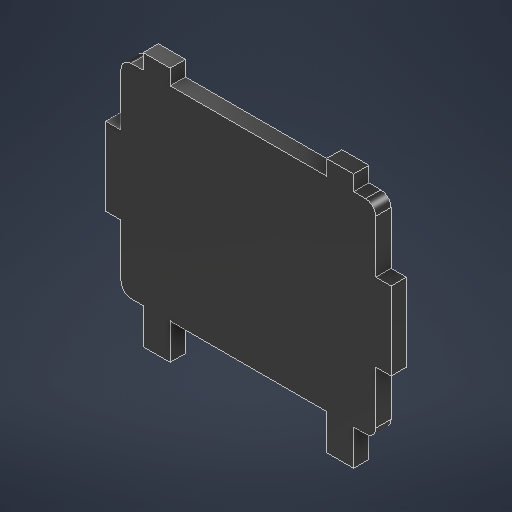
# Autodesk Inventor part: RxFace
Saved by Autodesk Inventor 2027.1 (Build 311270010, 270A)
## iProperties
Created: 2026-10-19
Part Number: RxFace
Material: MDF Medium Density Fiberboard
Document SubType Name: Modeling
Designer: SDS Scholar
Density: 0.8 g/cm^3
Appearance: Glossy - Black
Mass: 5.2603 g
Surface Area: 50.5383 cm^2
Volume: 6.57537 cm^3
Author: SDS Scholar
Autodesk Inventor part; units mm, degrees
ref_plane "YZ Plane" through (0, 0, 0) normal (1, 0, 0) x (0, 1, 0)
ref_plane "XZ Plane" through (0, 0, 0) normal (0, 1, 0) x (-1, 0, 0)
ref_plane "XY Plane" through (0, 0, 0) normal (0, 0, 1) x (1, 0, 0)
sketch "Sketch1" plane through (0, 0, 0) normal (0, 0, 1) x (1, 0, 0)
  line L0 (-25, 20) -> (25, 20)
  line L1 (25, 20) -> (25, -20)
  line L2 (25, -20) -> (-25, -20)
  line L3 (-25, -20) -> (-25, 20)
  line L4 (-25, 0) -> (25, 0) construction
  line L5 (0, 20) -> (0, -20) construction
  line L6 (-20.65, -20) -> (-15.35, -20)
  line L7 (-15.35, -20) -> (-15.35, -27)
  line L8 (-15.35, -27) -> (-20.65, -27)
  line L9 (-20.65, -27) -> (-20.65, -20)
  line L10 (-20.65, 20) -> (-15.35, 20)
  line L11 (-15.35, 20) -> (-15.35, 23)
  line L12 (-15.35, 23) -> (-20.65, 23)
  line L13 (-20.65, 23) -> (-20.65, 20)
  line L14 (-25, 7.65) -> (-28, 7.65)
  line L15 (-28, 7.65) -> (-28, -7.65)
  line L16 (-28, -7.65) -> (-25, -7.65)
  line L17 (-25, -7.65) -> (-25, 7.65)
  line L18 (15.35, -20) -> (15.35, -27)
  line L19 (15.35, -27) -> (20.65, -27)
  line L20 (20.65, -27) -> (20.65, -20)
  line L21 (15.35, 20) -> (15.35, 23)
  line L22 (15.35, 23) -> (20.65, 23)
  line L23 (20.65, 23) -> (20.65, 20)
  line L24 (25, 7.65) -> (28, 7.65)
  line L25 (28, 7.65) -> (28, -7.65)
  line L26 (28, -7.65) -> (25, -7.65)
  point P0 (0, 0)
  point P1 (-18, -27)
  point P2 (-18, 23)
  point P3 (-28, 0)
  point P4 (0, 0)
  point P5 (15.35, -20)
  point P6 (20.65, -20)
  point P7 (-15.35, 20)
  point P8 (-15.35, -20)
  point P9 (18, -27)
  dimension "d0" = 50
  dimension "d1" = 40
  dimension "d4" = 7
  dimension "d5" = 5.3
  dimension "d7" = 3
  dimension "d8" = 5.3
  dimension "d9" = 15.3
  dimension "d10" = 3
  dimension "d15" = 36
  constraints: 54 end point, 12 symmetric about line, 9 midpoint, 8 parallel, 5 horizontal, 4 perpendicular, 3 point on line, 2 horizontal alignment, 2 vertical alignment
  measures "d0" distance of L1.end L2.end
  measures "d1" distance of L0.end L1.end
  measures "d4" distance of L8.end L6.start
  measures "d5" distance of L7.end L8.end
  measures "d7" distance of L10.end L11.end
  measures "d8" distance of L11.end L12.end
  measures "d9" distance of L14.end L15.end
  measures "d10" distance of L15.end L16.end
  measures "d15" distance of point (18, -27) point (-18, -27)
extrude "Extrusion1" add sketch "Sketch1" along normal blind 3
fillet "Fillet1" [suppressed]
fillet "Fillet2" radius 2 4 edges at (-25, -20, 1.5) (25, -20, 1.5) (25, 20, 1.5) (-25, 20, 1.5)
equation "\"d0\" = Product_dia"
equation "\"d1\" = ProductBaseHeight"
equation "\"d4\" = BaseWoodThickness"
equation "\"Product_dia\" = 50"
equation "\"ProductBaseHeight\" = 40"
equation "\"BaseWoodThickness\" = 7"
body "Solid1"
